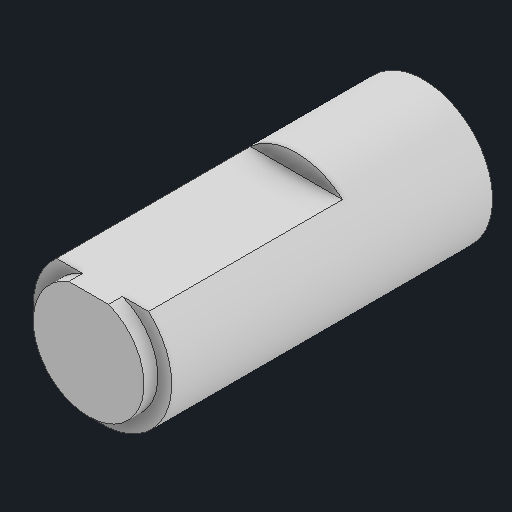
# Autodesk Inventor part: worm_shaft_stub_14p5
Saved by Autodesk Inventor 2027.1 (Build 311270010, 270A)
## iProperties
Created: 2026-11-11
Part Number: worm_shaft_stub_14p5
Material: Generic
Description: Brass worm shaft 6 mm, 14.5 mm from the block face, 9 mm past the nut (user measured 2026-11-11)
Document SubType Name: Modeling
Designer: alexg
Density: 1 g/cm^3
Appearance: Default
Author: alexg
Autodesk Inventor part; units mm, degrees
ref_plane "YZ Plane" through (0, 0, 0) normal (1, 0, 0) x (0, 1, 0)
sketch "Worm shaft 6mm sketch" plane through (0, 0, 0) normal (0, 0, 1) x (1, 0, 0)
  circle A0 centre (0, 0) radius 3
  constraints: 1 centre point
extrude "Worm shaft 6mm" add sketch "Worm shaft 6mm sketch" along normal blind 13.9
ref_plane "Work Plane1" through (0, 0, 13.9) normal (0, 0, 1) x (1, 0, 0)
sketch "Chamfered tip sketch" plane through (0, 0, 13.9) normal (0, 0, 1) x (1, 0, 0)
  circle A0 centre (0, 0) radius 2.4
  constraints: 1 centre point
extrude "Chamfered tip" add sketch "Chamfered tip sketch" along normal blind 0.6
ref_plane "Work Plane2" through (0, 2.24, 0) normal (0, 1, 0) x (-1, 0, 0)
sketch "Flat (4 wide) on the 9 mm stub sketch" plane through (0, 2.24, 0) normal (0, 1, 0) x (-1, 0, 0)
  line L0 (4, 5.5) -> (-4, 5.5)
  line L1 (-4, 5.5) -> (-4, 15.5)
  line L2 (-4, 15.5) -> (4, 15.5)
  line L3 (4, 15.5) -> (4, 5.5)
  constraints: 8 end point, 2 parallel, 1 horizontal, 1 perpendicular
extrude "Flat (4 wide) on the 9 mm stub" cut sketch "Flat (4 wide) on the 9 mm stub sketch" along normal blind 2
body "Solid1"
